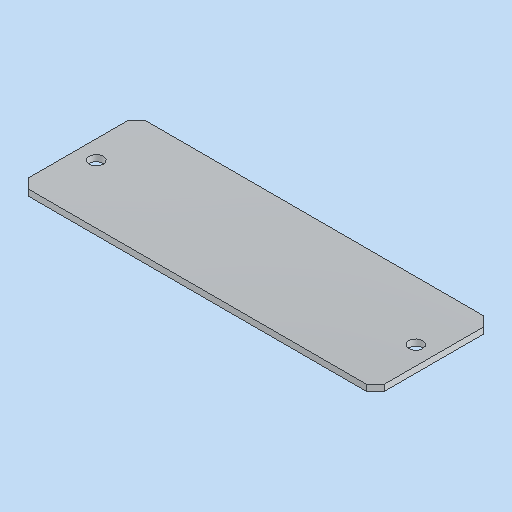
# Autodesk Inventor part: MM0948AN100_G01_207
Saved by Autodesk Inventor 2023.3 (Build 273359000, 359)
## iProperties
Created: 2023-11-30
Part Number: MM0948AN100_G01_207
Material: 3.3535 AlMg3 - AW 5754 (Blech)
Description: =<RBPARTNOTITLE2>
Document SubType Name: Sheet Metal
Designer: RIC7AN
Mass: 23.3204 g
Surface Area: 92.9487 cm^2
Volume: 8.64038 cm^3
Density: 2.699 g/cm^3
Sheet Metal Rule: Standard_mm
Appearance: Aluminium AnP
RBPARTMADEOF: 2 x 38 x 115 (FM)
RBDRAWINGMISSINGSPEC: --
AnP_Kategorie: 1
RBPARTNOTITLE2: Anfertigungsteil
RBSURFACE: anodised E6/EV1 colourless
RBPARTNOTITLE1: manufactured part
RBSURFACE2: eloxiert E6/EV1 aluminiumfarbig
AnP_Material: =<Material>
RBMATERIAL: =<Material>
RBMATNO: =<Part Number>
RBPARTNO: SIEHE MNR
MaxAbmaße: 2 x 38 x 115 (FM)
Author: RIC7AN
Keywords: =<RBPARTMADEOF>
Comments: =<RBSURFACE2>
Revision Number: 01
Autodesk Inventor part; units mm, degrees
ref_plane "YZ Plane" through (0, 0, 0) normal (1, 0, 0) x (0, 1, 0)
ref_plane "XZ Plane" through (0, 0, 0) normal (0, 1, 0) x (-1, 0, 0)
ref_plane "XY Plane" through (0, 0, 0) normal (0, 0, 1) x (1, 0, 0)
sketch "Skizze1" plane through (0, 0, 0) normal (0, 0, 1) x (1, 0, 0)
  line L0 (-57.5, 19) -> (57.5, 19)
  line L1 (57.5, 19) -> (57.5, -19)
  line L2 (57.5, -19) -> (-57.5, -19)
  line L3 (-57.5, -19) -> (-57.5, 19)
  line L4 (0, 26.6) -> (0, -26.6)
  line L5 (-80.5, 0) -> (80.5, 0)
  point P0 (0, 0)
  dimension "d0" = 115
  dimension "d1" = 38
  measures "d0" distance of L0.start L0.end
  measures "d1" distance of L0.end L1.end
extrude "Grobblech1" add sketch "Skizze1" along normal blind 2
chamfer "Eckenfase1" distance 3 angle 45 4 edges at (-57.5, -19, 1) (-57.5, 19, 1) (57.5, -19, 1) (57.5, 19, 1)
sketch "Skizze2" plane through (0, 0, 2) normal (0, 0, 1) x (1, 0, 0)
  line L0 (0, 26.6) -> (0, -26.6) projected
  line L1 (-80.5, 0) -> (80.5, 0) projected
  point P0 (0, 0)
  point P1 (-51.5, 0)
  point P2 (51.5, 0)
  dimension "d6" = 103
  constraints: 2 point on line, 1 symmetric about line
  measures "d6" distance of point (51.5, 0) point (-51.5, 0)
hole "Bohrung1" at (-51.5, 0, 2) at (51.5, 0, 2) direction (0, 0, -1) diameter 4.5 end through all clearance for "Inbusschraube ISO 4762  versenkt" size "M4" standard "ISO"
equation "\"d12\" = Stärke"
equation "\"d2\" = Stärke"
equation "\"Biegeradius\" = Stärke"
equation "\"BreiteBiegungsfreistellung\" = Stärke"
equation "\"TiefeBiegungsfreistellung\" = 0.5 * Stärke"
equation "\"GrößeEckenfreistellung\" = 4 * Stärke"
equation "\"MinimalRest\" = 2 * Stärke"
equation "\"Übergangsradius\" = Biegeradius"
equation "\"JacobiRadiusGröße\" = Biegeradius"
equation "\"Abstandsgröße\" = Stärke"
equation "\"Stärke\" = 2"
